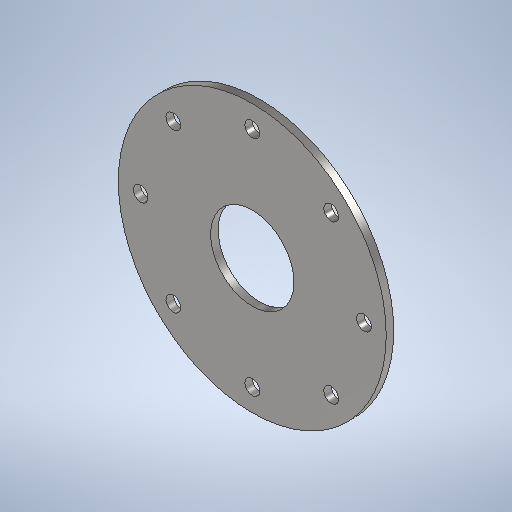
# Autodesk Inventor part: DMF-1216 Flange 01
Saved by Autodesk Inventor 2026.2 (Build 302298000, 298)
## iProperties
Created: 2026-11-05
Part Number: DMF-1216 Flange 01
Material: Stainless Steel
Document SubType Name: Sheet Metal
Designer: admin
Stock Number: DMF-1216
Mass: 891.678 g
Surface Area: 496.89 cm^2
Volume: 111.46 cm^3
Density: 8 g/cm^3
Flat Pattern Width: 18 cm
Flat Pattern Length: 18 cm
Flat Pattern Area: 324 cm^2
Sheet Metal Rule: Default
Sheet Metal Width: 180,000 mm
Sheet Metal Length: 180,000 mm
Sheet Metal Area: 32400,000 mm^2
Appearance: Semi-Polished
Author: admin
Autodesk Inventor part; units mm, degrees
ref_plane "YZ Plane" through (0, 0, 0) normal (1, 0, 0) x (0, 1, 0)
ref_plane "XZ Plane" through (0, 0, 0) normal (0, 1, 0) x (-1, 0, 0)
ref_plane "XY Plane" through (0, 0, 0) normal (0, 0, 1) x (1, 0, 0)
sketch "Sketch Flange" plane through (0, 0, 0) normal (0, 0, 1) x (1, 0, 0)
  circle A0 centre (0, 0) radius 90
  circle A1 centre (0, 0) radius 28
  dimension "d0" = 180
  dimension "d1" = 56
  measures "d0" diameter of A0
  measures "d1" diameter of A1
extrude "Plate1" add sketch "Sketch Flange" along normal blind 5
sketch "Sketch Bolt Hole" plane through (0, 0, 5) normal (0, 0, 1) x (1, 0, 0)
  line L0 (0, -126) -> (0, 126) construction
  circle A0 centre (0, 75) radius 5
  line L1 (0, 0) -> (0, 75) construction
  dimension "d5" = 10
  dimension "d6" = 75
  constraints: 2 end point, 1 centre point, 1 point on line
  measures "d5" diameter of A0
  measures "d6" distance of L1.start L1.end
extrude "Cut Bolt Hole" cut sketch "Sketch Bolt Hole" against normal blind 5
pattern_circular "Pattern Bolt Holes" count 8 over 360 about axis through (0, 0, -10) along (0, 0, 1) of "Cut Bolt Hole"
equation "\"d0\" = Flange_Outer_Diameter"
equation "\"d1\" = Flange_Coupling_Hole_Diameter"
equation "\"d5\" = Flange_Bolt_Hole_Diameter"
equation "\"d6\" = 0.5 * Flange_Bolt_Circle_Diameter"
equation "\"d4\" = Thickness"
equation "\"BendRadius\" = Thickness"
equation "\"BendReliefWidth\" = Thickness"
equation "\"BendReliefDepth\" = 0.5 * Thickness"
equation "\"TransitionRadius\" = BendRadius"
equation "\"JacobiRadiusSize\" = BendRadius"
equation "\"GapSize\" = Thickness"
equation "\"Flange_Outer_Diameter\" = 180"
equation "\"Flange_Bolt_Hole_Diameter\" = 10"
equation "\"Flange_Coupling_Hole_Diameter\" = 56"
equation "\"Flange_Nut_Hole_Diameter\" = 9"
equation "\"Flange_Bolt_Circle_Diameter\" = 150"
equation "\"Thickness\" = 5"
body "Solid1"
